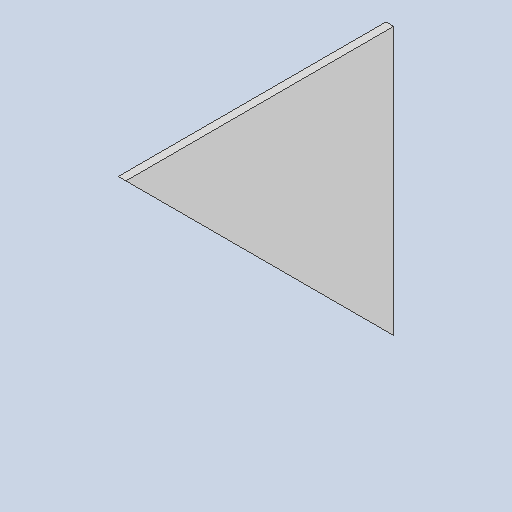
# Autodesk Inventor part: RDS-GHN300-1002 Container shelf rib3
Saved by Autodesk Inventor 2026 (Build 300175000, 175)
## iProperties
Created: 2026-10-27
Part Number: RDS-GHN300-1002 Container shelf rib3
Material: Типовые
Document SubType Name: Modeling
Designer: user
Density: 1 g/cm^3
Appearance: По умолчанию
Author: user
Autodesk Inventor part; units mm, degrees
ref_plane "YZ Plane" through (0, 0, 0) normal (1, 0, 0) x (0, 1, 0)
ref_plane "XZ Plane" through (0, 0, 0) normal (0, 1, 0) x (-1, 0, 0)
ref_plane "XY Plane" through (0, 0, 0) normal (0, 0, 1) x (1, 0, 0)
sketch "Эскиз1" plane through (0, 0, 0) normal (1, 0, 0) x (0, 1, 0)
  line L0 (0, 0) -> (-350, 0)
  line L1 (0, 0) -> (0, 350)
  line L2 (0, 350) -> (-350, 0)
  dimension "d0" = 350
  dimension "d1" = 350
  constraints: 6 end point, 1 horizontal, 1 vertical
  measures "d0" distance of L0.start L0.end
  measures "d1" distance of L0.start L1.end
extrude "Выдавливание1" add sketch "Эскиз1" against normal blind 10
